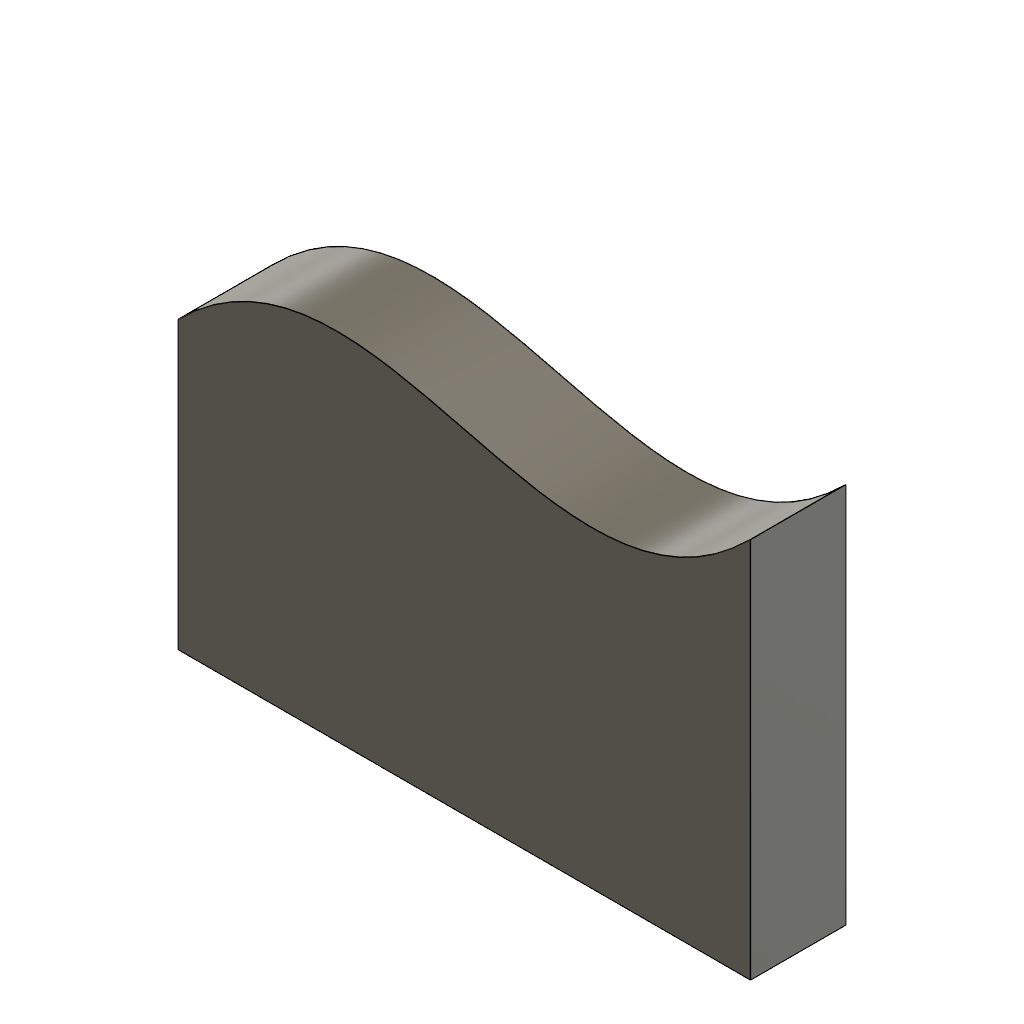
sk_spline_control_point (Autodesk Fusion 360 design; units mm, degrees)
part number: 2026-11-13-14-36-17-291
Autodesk Fusion 360 part; units mm, degrees
sketch "Sketch1" plane through (0, 0, 0) normal (0, 0, 1) x (1, 0, 0)
  line L0 (0, 0) -> (10, 10) construction
  line L1 (10, 10) -> (20, -5) construction
  line L2 (20, -5) -> (30, 5) construction
  spline S0 degree 3 poles (0, 0) (10, 10) (20, -5) (30, 5) knots 0 0 0 0 1 1 1 1
  line L3 (30, 5) -> (30, -15)
  line L4 (30, -15) -> (0, -15)
  line L5 (0, -15) -> (0, 0)
extrude "Extrude1" add sketch "Sketch1" along normal blind 5
